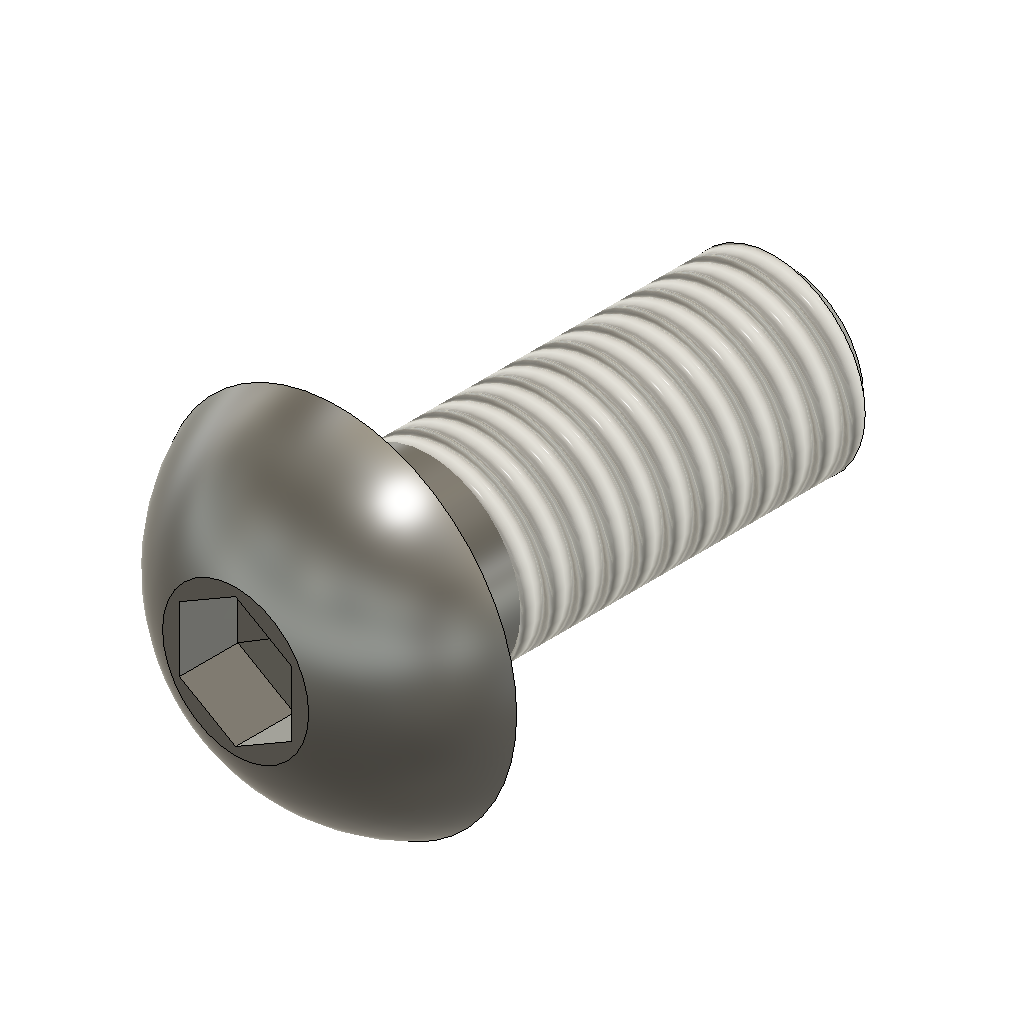
cnc (Autodesk Fusion 360 archive; units mm, degrees)
design "Hexagon Socket Button Head Screw ISO 7380-1 - M5 x 12 Steel 4.6 Plain"
description: Hexagon Socket Button Head Screw ISO 7380-1 - M5 x 12
part number: ISO 7380-1 - M5 x 12 Steel 4.6 Plain
Autodesk Fusion 360 part; units mm, degrees
sketch "Sketch1" plane through (0, 0, 0) normal (0, 1, 0) x (1, 0, 0)
  line L0 (-2.5, 0) -> (-2.5, 12)
  line L1 (-2.5, 12) -> (0, 12)
  line L2 (0, 12) -> (0, -2.75)
  line L3 (-2.5, 0) -> (-4.75, 0)
  line L4 (0, -2.75) -> (-1.95, -2.75)
  arc A0 (-4.75, 0) -> (-1.95, -2.75) centre (0, 2.0359) ccw
  dimension "d9" = 5
  dimension "d66" = 9.5
  dimension "d98" = 3.9
  dimension "d105" = 2.75
  dimension "d106" = 12
  constraint perpendicular L0 L1
  constraint perpendicular L0 L3
  constraint coincident origin L3
  constraint vertical L0
  constraint vertical L2
  constraint coincident origin L2
  constraint perpendicular L2 L4
  constraint coincident L2 A0.centre
  measures "d105" distance of L3 L4
  measures "d106" distance of origin L1
revolve "Revolve1" add sketch "Sketch1" angle 360 about axis through (0, 0, -12) along (0, 0, 1)
ref_plane "WorkPlane1" through (0, 0, 2.75) normal (0, 0, 1) x (1, 0, 0)
sketch "Sketch6" plane through (0, 0, 2.75) normal (0, 0, 1) x (1, 0, 0)
  line L0 (0, -1.7321) -> (1.5, -0.866)
  line L1 (1.5, -0.866) -> (1.5, 0.866)
  line L2 (1.5, 0.866) -> (0, 1.7321)
  line L3 (0, 1.7321) -> (-1.5, 0.866)
  line L4 (-1.5, 0.866) -> (-1.5, -0.866)
  line L5 (-1.5, -0.866) -> (0, -1.7321)
  dimension "d117" = 3
  constraint vertical L1
  measures "d117" distance of L1 L4
extrude "Extrude1" cut sketch "Sketch6" against normal blind 1.56
extrude "Extrude2" cut 1 faces at (0.5, 0.2887, 1.19) along direction (0, 0, -1) blind 1.56 draft -85
fillet "Fillet5" radius 0.45 1 edges at (-2.3308, 0.904, 0)
thread "Thread5" "ISO Metric profile 5.0 M5x0.8 M5x0.8 6g" major diameter 4.901 minor diameter 3.9895 pitch 0.8 angle 60 resizes the face on face at (-2.4876, 0.2489, -8.15) from (0, 0, -2.4) to (0, 0, -12)
sketch "Sketch5" plane through (0, 0, 0) normal (0, 1, 0) x (1, 0, 0)
  line L0 (0, 12) -> (0, -2.75)
  line L1 (0, 12) -> (-2.55, 12)
  line L2 (-2.55, 12) -> (-2.55, 11.5092)
  line L3 (-2.55, 11.5092) -> (-2.0092, 12)
  dimension "d108" = 0.4908
  dimension "d109" = 2.0092
  dimension "d110" = 2.55
  constraint coincident L0.start L1.start
  constraint perpendicular L1 L2
  constraint coincident L1 L3.end
  measures "d108" distance of L1 L2.end
  measures "d109" distance of L0 L3.end
  measures "d110" distance of L0 L2
revolve "Revolve2" cut sketch "Sketch5" angle 360 about axis through (0, 0, -12) along (0, 0, 1)
equation "d9 = adsk_nomdia"
equation "adsk_nomlen = 12.00 mm"
equation "adsk_headh = 2.75 mm"
equation "adsk_headdia = 9.50 mm"
equation "adsk_nomdia = 5.00 mm"
equation "adsk_philwidth = 3.00 mm"
equation "d31 = -adsk_phildepth"
equation "adsk_phildepth = 1.56 mm"
equation "d66 = adsk_headdia"
equation "d71 = adsk_headh"
equation "d76 = -adsk_phildepth"
equation "adsk_thrlen = 9.60 mm"
equation "adsk_endpointdia = 4.01848 mm"
equation "adsk_startlen = 0.49076 mm"
equation "d98 = adsk_philwidth * 1.3"
equation "adsk_midfillet = 0.45 mm"
equation "d104 = adsk_midfillet"
equation "d105 = adsk_headh"
equation "d106 = adsk_nomlen"
equation "d108 = adsk_startlen"
equation "d109 = adsk_endpointdia / 2"
equation "d110 = adsk_nomdia * 0.51"
equation "d116 = min(adsk_thrlen; adsk_nomlen - adsk_midfillet - 0.001 mm)"
equation "d117 = adsk_philwidth"

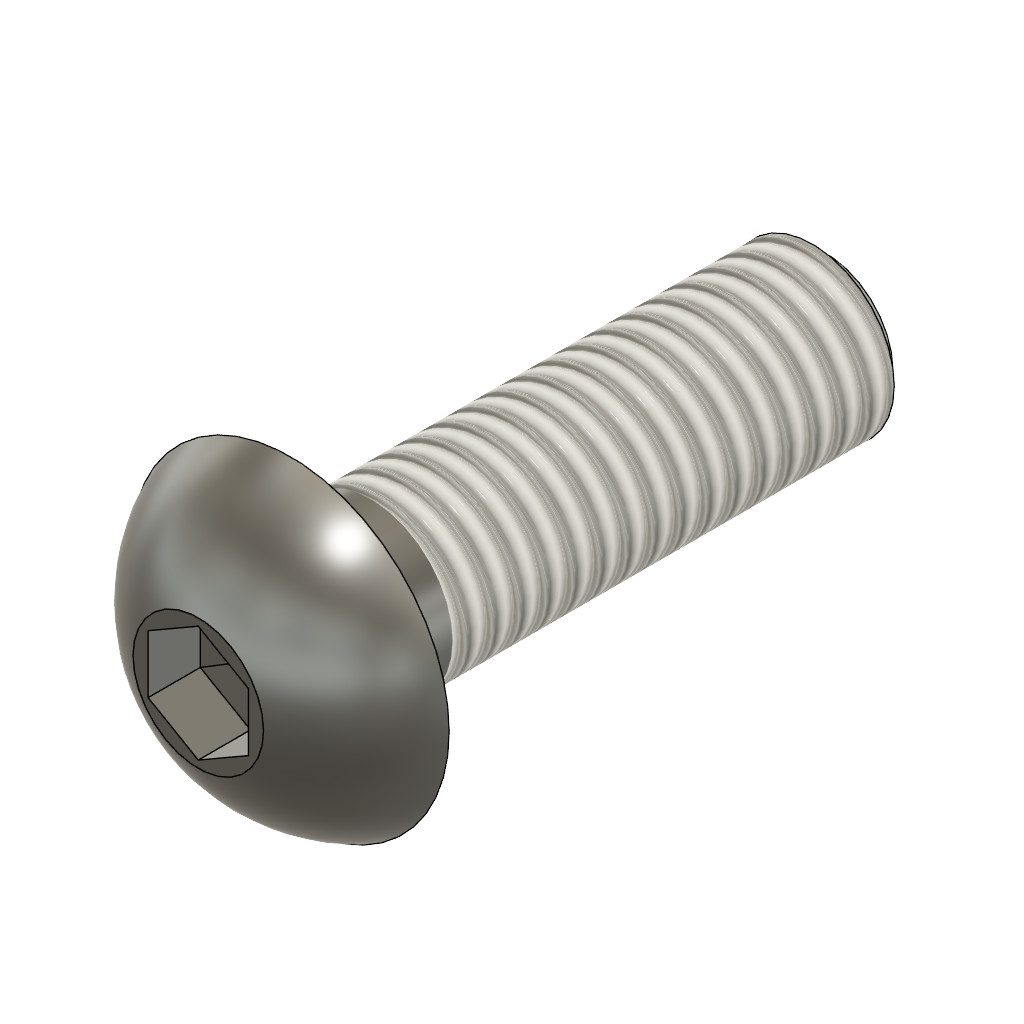
design "Hexagon Socket Button Head Screw ISO 7380-1 - M5 x 16 Steel 4.6 Plain"
description: Hexagon Socket Button Head Screw ISO 7380-1 - M5 x 16
part number: ISO 7380-1 - M5 x 16 Steel 4.6 Plain
Autodesk Fusion 360 part; units mm, degrees
sketch "Sketch1" plane through (0, 0, 0) normal (0, 1, 0) x (1, 0, 0)
  line L0 (-2.5, 0) -> (-2.5, 16)
  line L1 (-2.5, 16) -> (0, 16)
  line L2 (0, 16) -> (0, -2.75)
  line L3 (-2.5, 0) -> (-4.75, 0)
  line L4 (0, -2.75) -> (-1.95, -2.75)
  arc A0 (-4.75, 0) -> (-1.95, -2.75) centre (0, 2.0359) ccw
  dimension "d9" = 5
  dimension "d66" = 9.5
  dimension "d98" = 3.9
  dimension "d105" = 2.75
  dimension "d106" = 16
  constraint perpendicular L0 L1
  constraint perpendicular L0 L3
  constraint coincident origin L3
  constraint vertical L0
  constraint vertical L2
  constraint coincident origin L2
  constraint perpendicular L2 L4
  constraint coincident L2 A0.centre
  measures "d105" distance of L3 L4
  measures "d106" distance of origin L1
revolve "Revolve1" add sketch "Sketch1" angle 360 about axis through (0, 0, -16) along (0, 0, 1)
ref_plane "WorkPlane1" through (0, 0, 2.75) normal (0, 0, 1) x (1, 0, 0)
sketch "Sketch6" plane through (0, 0, 2.75) normal (0, 0, 1) x (1, 0, 0)
  line L0 (0, -1.7321) -> (1.5, -0.866)
  line L1 (1.5, -0.866) -> (1.5, 0.866)
  line L2 (1.5, 0.866) -> (0, 1.7321)
  line L3 (0, 1.7321) -> (-1.5, 0.866)
  line L4 (-1.5, 0.866) -> (-1.5, -0.866)
  line L5 (-1.5, -0.866) -> (0, -1.7321)
  dimension "d117" = 3
  constraint vertical L1
  measures "d117" distance of L1 L4
extrude "Extrude1" cut sketch "Sketch6" against normal blind 1.56
extrude "Extrude2" cut 1 faces at (0.5, 0.2887, 1.19) along direction (0, 0, -1) blind 1.56 draft -85
fillet "Fillet5" radius 0.45 1 edges at (-2.3308, 0.904, 0)
thread "Thread5" "ISO Metric profile 5.0 M5x0.8 M5x0.8 6g" major diameter 4.901 minor diameter 3.9895 pitch 0.8 angle 60 resizes the face on face at (-2.4969, 0.1246, -10.8167) from (0, 0, -2.4) to (0, 0, -16)
sketch "Sketch5" plane through (0, 0, 0) normal (0, 1, 0) x (1, 0, 0)
  line L0 (0, 16) -> (0, -2.75)
  line L1 (0, 16) -> (-2.55, 16)
  line L2 (-2.55, 16) -> (-2.55, 15.5092)
  line L3 (-2.55, 15.5092) -> (-2.0092, 16)
  dimension "d108" = 0.4908
  dimension "d109" = 2.0092
  dimension "d110" = 2.55
  constraint coincident L0.start L1.start
  constraint perpendicular L1 L2
  constraint coincident L1 L3.end
  measures "d108" distance of L1 L2.end
  measures "d109" distance of L0 L3.end
  measures "d110" distance of L0 L2
revolve "Revolve2" cut sketch "Sketch5" angle 360 about axis through (0, 0, -16) along (0, 0, 1)
equation "d9 = adsk_nomdia"
equation "adsk_nomlen = 16.00 mm"
equation "adsk_headh = 2.75 mm"
equation "adsk_headdia = 9.50 mm"
equation "adsk_nomdia = 5.00 mm"
equation "adsk_philwidth = 3.00 mm"
equation "d31 = -adsk_phildepth"
equation "adsk_phildepth = 1.56 mm"
equation "d66 = adsk_headdia"
equation "d71 = adsk_headh"
equation "d76 = -adsk_phildepth"
equation "adsk_thrlen = 13.60 mm"
equation "adsk_endpointdia = 4.01848 mm"
equation "adsk_startlen = 0.49076 mm"
equation "d98 = adsk_philwidth * 1.3"
equation "adsk_midfillet = 0.45 mm"
equation "d104 = adsk_midfillet"
equation "d105 = adsk_headh"
equation "d106 = adsk_nomlen"
equation "d108 = adsk_startlen"
equation "d109 = adsk_endpointdia / 2"
equation "d110 = adsk_nomdia * 0.51"
equation "d116 = min(adsk_thrlen; adsk_nomlen - adsk_midfillet - 0.001 mm)"
equation "d117 = adsk_philwidth"

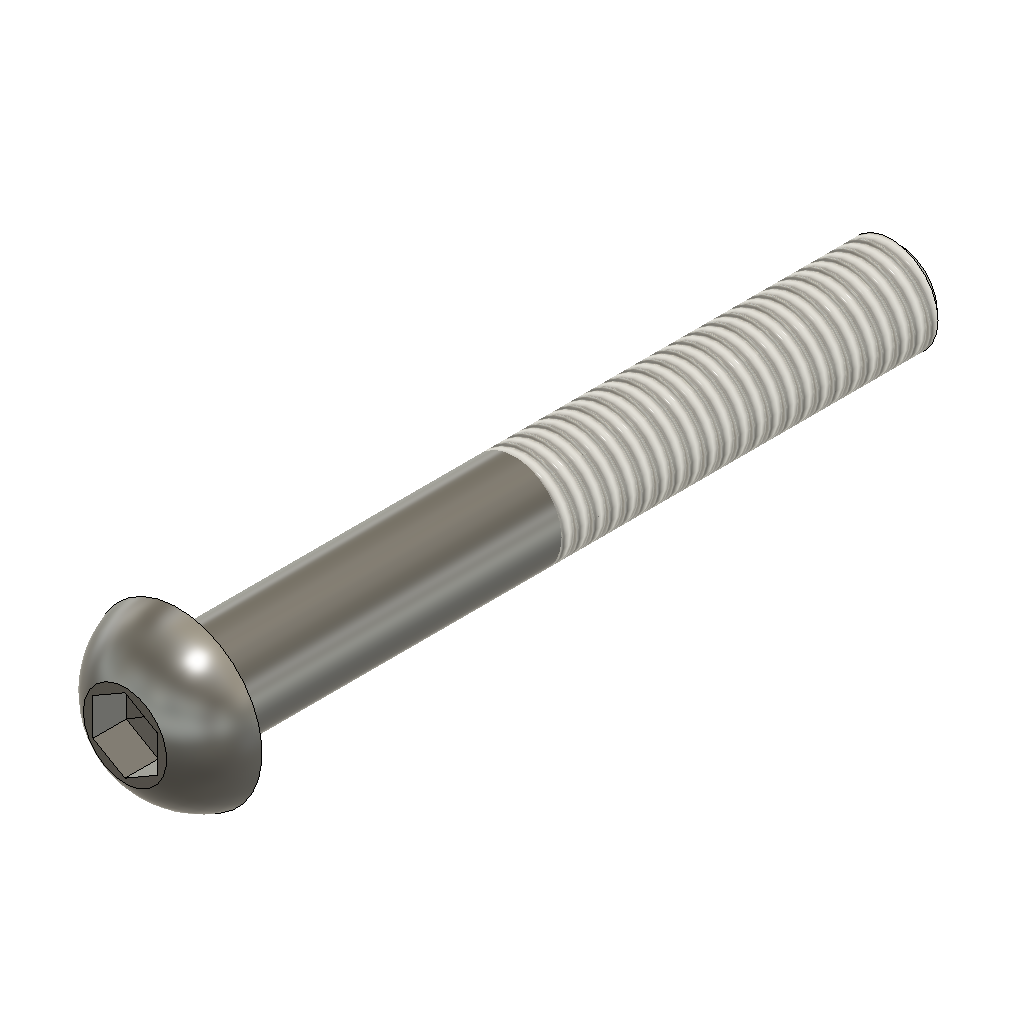
design "Hexagon Socket Button Head Screw ISO 7380-1 - M6 x 45 Steel 4.6 Plain"
description: Hexagon Socket Button Head Screw ISO 7380-1 - M6 x 45
part number: ISO 7380-1 - M6 x 45 Steel 4.6 Plain
Autodesk Fusion 360 part; units mm, degrees
sketch "Sketch1" plane through (0, 0, 0) normal (0, 1, 0) x (1, 0, 0)
  line L0 (-3, 0) -> (-3, 45)
  line L1 (-3, 45) -> (0, 45)
  line L2 (0, 45) -> (0, -3.3)
  line L3 (-3, 0) -> (-5.25, 0)
  line L4 (0, -3.3) -> (-2.6, -3.3)
  arc A0 (-5.25, 0) -> (-2.6, -3.3) centre (0, 1.5019) ccw
  dimension "d9" = 6
  dimension "d66" = 10.5
  dimension "d98" = 5.2
  dimension "d105" = 3.3
  dimension "d106" = 45
  constraint perpendicular L0 L1
  constraint perpendicular L0 L3
  constraint coincident origin L3
  constraint vertical L0
  constraint vertical L2
  constraint coincident origin L2
  constraint perpendicular L2 L4
  constraint coincident L2 A0.centre
  measures "d105" distance of L3 L4
  measures "d106" distance of origin L1
revolve "Revolve1" add sketch "Sketch1" angle 360 about axis through (0, 0, -45) along (0, 0, 1)
ref_plane "WorkPlane1" through (0, 0, 3.3) normal (0, 0, 1) x (1, 0, 0)
sketch "Sketch6" plane through (0, 0, 3.3) normal (0, 0, 1) x (1, 0, 0)
  line L0 (0, -2.3094) -> (2, -1.1547)
  line L1 (2, -1.1547) -> (2, 1.1547)
  line L2 (2, 1.1547) -> (0, 2.3094)
  line L3 (0, 2.3094) -> (-2, 1.1547)
  line L4 (-2, 1.1547) -> (-2, -1.1547)
  line L5 (-2, -1.1547) -> (0, -2.3094)
  dimension "d117" = 4
  constraint vertical L1
  measures "d117" distance of L1 L4
extrude "Extrude1" cut sketch "Sketch6" against normal blind 2.08
extrude "Extrude2" cut 1 faces at (0.6667, 0.3849, 1.22) along direction (0, 0, -1) blind 2.08 draft -85
fillet "Fillet5" radius 0.25 1 edges at (-2.797, 1.0848, 0)
thread "Thread5" "ISO Metric profile 6.0 M6x1 M6x1 6g" major diameter 5.884 minor diameter 4.7435 pitch 1 angle 60 resizes the face on face at (-2.9851, 0.2987, -30.0833) from (0, 0, -21) to (0, 0, -45)
sketch "Sketch5" plane through (0, 0, 0) normal (0, 1, 0) x (1, 0, 0)
  line L0 (0, 45) -> (0, -3.3)
  line L1 (0, 45) -> (-3.06, 45)
  line L2 (-3.06, 45) -> (-3.06, 44.3866)
  line L3 (-3.06, 44.3866) -> (-2.3866, 45)
  dimension "d108" = 0.6135
  dimension "d109" = 2.3866
  dimension "d110" = 3.06
  constraint coincident L0.start L1.start
  constraint perpendicular L1 L2
  constraint coincident L1 L3.end
  measures "d108" distance of L1 L2.end
  measures "d109" distance of L0 L3.end
  measures "d110" distance of L0 L2
revolve "Revolve2" cut sketch "Sketch5" angle 360 about axis through (0, 0, -45) along (0, 0, 1)
equation "d9 = adsk_nomdia"
equation "adsk_nomlen = 45.00 mm"
equation "adsk_headh = 3.30 mm"
equation "adsk_headdia = 10.50 mm"
equation "adsk_nomdia = 6.00 mm"
equation "adsk_philwidth = 4.00 mm"
equation "d31 = -adsk_phildepth"
equation "adsk_phildepth = 2.08 mm"
equation "d66 = adsk_headdia"
equation "d71 = adsk_headh"
equation "d76 = -adsk_phildepth"
equation "adsk_thrlen = 24.00 mm"
equation "adsk_endpointdia = 4.7731 mm"
equation "adsk_startlen = 0.61345 mm"
equation "d98 = adsk_philwidth * 1.3"
equation "adsk_midfillet = 0.25 mm"
equation "d104 = adsk_midfillet"
equation "d105 = adsk_headh"
equation "d106 = adsk_nomlen"
equation "d108 = adsk_startlen"
equation "d109 = adsk_endpointdia / 2"
equation "d110 = adsk_nomdia * 0.51"
equation "d116 = min(adsk_thrlen; adsk_nomlen - adsk_midfillet - 0.001 mm)"
equation "d117 = adsk_philwidth"
